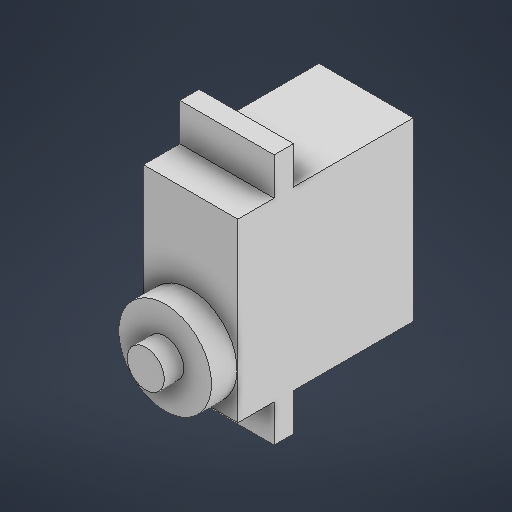
# Autodesk Inventor part: DUMMY-MG90S
Saved by Autodesk Inventor 2027.1 (Build 311270010, 270A)
## iProperties
Created: 2026-10-28
Part Number: DUMMY-MG90S
Material: Generic
Description: MG90S servo dummy (case, tabs, gear dome, spline)
Document SubType Name: Modeling
Designer: shyan
Mass: 13.4 g
Surface Area: 25.929 cm^2
Volume: 7.02854 cm^3
Density: 1.90651 g/cm^3
Appearance: Default
Author: shyan
Autodesk Inventor part; units mm, degrees
sketch "sk_case" plane through (0, 0, 0) normal (0, 0, 1) x (1, 0, 0)
  line L0 (-6.1, -5.9) -> (6.1, -5.9)
  line L1 (6.1, -5.9) -> (6.1, 16.9)
  line L2 (6.1, 16.9) -> (-6.1, 16.9)
  line L3 (-6.1, 16.9) -> (-6.1, -5.9)
  line L4 (0, -11.58) -> (0, 23.98) construction
  point P0 (0, 0)
  dimension "d13" = 12.2
  dimension "d14" = 22.8
  dimension "d15" = 5.9
  constraints: 8 end point, 2 parallel, 1 horizontal, 1 perpendicular, 1 other
  measures "d13" distance of L0.start L0.end
  measures "d14" distance of L0.end L1.end
  measures "d15" vertical distance of point (0, 0) L0.start
extrude "Case" add sketch "sk_case" along normal blind 22.7
ref_plane "Work Plane1" through (0, 0, 15.5) normal (0, 0, 1) x (1, 0, 0)
sketch "sk_tabs" plane through (0, 0, 15.5) normal (0, 0, 1) x (1, 0, 0)
  line L0 (-6.1, -10.75) -> (6.1, -10.75)
  line L1 (6.1, -10.75) -> (6.1, 21.75)
  line L2 (6.1, 21.75) -> (-6.1, 21.75)
  line L3 (-6.1, 21.75) -> (-6.1, -10.75)
  line L4 (-8.54, 0) -> (8.54, 0) construction
  line L5 (0, -16.55) -> (0, 28.95) construction
  point P0 (0, 0)
  dimension "d25" = 12.2
  dimension "d26" = 32.5
  dimension "d27" = 10.75
  constraints: 8 end point, 2 parallel, 1 horizontal, 1 perpendicular, 1 other
  measures "d25" distance of L0.start L0.end
  measures "d26" distance of L0.end L1.end
  measures "d27" vertical distance of point (0, 0) L0.start
extrude "Tabs" add sketch "sk_tabs" along normal blind 2.5
ref_plane "sk_dome_plane" through (0, 0, 22.7) normal (0, 0, 1) x (1, 0, 0)
sketch "sk_dome" plane through (0, 0, 22.7) normal (0, 0, 1) x (1, 0, 0)
  circle A0 centre (0, 0) radius 6
  dimension "d18" = 12
  constraints: 1 centre point, 1 other
  measures "d18" diameter of A0
extrude "Dome" add sketch "sk_dome" along normal blind 3.3
ref_plane "sk_spline_plane" through (0, 0, 26) normal (0, 0, 1) x (1, 0, 0)
sketch "sk_spline" plane through (0, 0, 26) normal (0, 0, 1) x (1, 0, 0)
  circle A0 centre (0, 0) radius 2.4
  dimension "d22" = 4.8
  constraints: 1 centre point, 1 other
  measures "d22" diameter of A0
extrude "Spline" add sketch "sk_spline" along normal blind 2.5
equation "\"d13\" = sv_W"
equation "\"d14\" = sv_L"
equation "\"d15\" = sv_shaft"
equation "\"d0\" = sv_H"
equation "\"d25\" = sv_W"
equation "\"d26\" = sv_tab"
equation "\"d27\" = -0.5 * sv_L + 0.5 * sv_tab + sv_shaft"
equation "\"d3\" = sv_tabT"
equation "\"d18\" = sv_dome"
equation "\"d19\" = sv_domeH"
equation "\"d22\" = sv_spline"
equation "\"d23\" = -sv_H + sv_full - sv_domeH"
equation "\"sv_L\" = 22.8"
equation "\"sv_W\" = 12.2"
equation "\"sv_H\" = 22.7"
equation "\"sv_full\" = 28.5"
equation "\"sv_tab\" = 32.5"
equation "\"sv_tabT\" = 2.5"
equation "\"sv_tabZ\" = 15.5"
equation "\"sv_shaft\" = 5.9"
equation "\"sv_dome\" = 12"
equation "\"sv_domeH\" = 3.3"
equation "\"sv_spline\" = 4.8"
equation "\"d2\" = sv_tabZ"
equation "\"d17\" = sv_H"
equation "\"d21\" = sv_H + sv_domeH"
body "Solid1"
